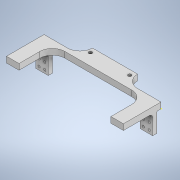
# Autodesk Inventor part: suport sfoara usa
Saved by Autodesk Inventor 2022.6 (Build 266554000, 554)
## iProperties
Created: 2025-02-05
Part Number: suport sfoara usa
Material: Generic
Document SubType Name: Modeling
Designer: Dragos Macovei
Density: 1 g/cm^3
Appearance: Default
Author: Dragos Macovei
Autodesk Inventor part; units mm, degrees
ref_plane "YZ Plane" through (0, 0, 0) normal (1, 0, 0) x (0, 1, 0)
ref_plane "XZ Plane" through (0, 0, 0) normal (0, 1, 0) x (-1, 0, 0)
ref_plane "XY Plane" through (0, 0, 0) normal (0, 0, 1) x (1, 0, 0)
sketch "Sketch1" plane through (0, 0, 0) normal (0, 0, 1) x (1, 0, 0)
  line L0 (0, 0) -> (-140, 0)
  line L1 (-140, 0) -> (-140, 7)
  line L2 (-140, 7) -> (0, 7)
  line L3 (0, 7) -> (0, 0)
  dimension "d0" = 140
  dimension "d1" = 7
  constraints: 8 end point, 2 parallel, 1 horizontal, 1 perpendicular
  measures "d0" distance of L1.end L2.end
  measures "d1" distance of L0.end L1.end
extrude "Extrusion1" add sketch "Sketch1" along normal blind 5
sketch "Sketch2" plane through (0, 0, 0) normal (0, 0, -1) x (-1, 0, 0)
  point P0 (0, 0)
sketch "Sketch3" plane through (0, 0, 5) normal (0, 0, 1) x (1, 0, 0)
  line L0 (0, 7) -> (-140, 7) projected
  line L1 (-140, 7) -> (-140, 0) projected
  line L2 (-140, 0) -> (0, 0) projected
  line L3 (0, 0) -> (0, 7) projected
  line L4 (-140, 7) -> (-140, 0) projected
  line L5 (-140, 7) -> (-125, 7)
  line L6 (-125, 7) -> (-125, -23)
  line L7 (-125, -23) -> (-140, -23)
  line L8 (-140, -23) -> (-140, 7)
  line L9 (0, 7) -> (-15, 7)
  line L10 (-15, 7) -> (-15, -23)
  line L11 (-15, -23) -> (0, -23)
  line L12 (0, -23) -> (0, 7)
  dimension "d4" = 15
  dimension "d5" = 30
  dimension "d6" = 15
  dimension "d7" = 30
  constraints: 16 end point, 4 parallel, 2 horizontal, 2 perpendicular
  measures "d4" distance of L6.end L7.end
  measures "d5" distance of L5.end L6.end
  measures "d6" distance of L11.end L10.end
  measures "d7" distance of L10.end L9.end
extrude "Extrusion2" add sketch "Sketch3" along normal blind 40 contours L3 L2 L10 L0 | L12 L11 L10 L2 | L6 L2 L1 L0 | L6 L7 L8 L2
fillet "Fillet1" radius 15 2 edges at (-125, 3.5, 5) (-15, 3.5, 5)
fillet "Fillet2" radius 1 2 edges at (-7.5, 0, 5) (-132.5, 0, 5)
sketch "Sketch4" plane through (-140, 7, 0) normal (0, 1, 0) x (1, 0, 0)
  line L0 (140, 0) -> (0, 0) projected
  line L1 (110, -5) -> (30, -5) projected
  line L2 (70, -5) -> (70, 0)
  line L3 (50, -5) -> (90, -5)
  line L4 (90, -5) -> (90, 0)
  line L5 (90, 0) -> (50, 0)
  line L6 (50, 0) -> (50, -5)
  point P0 (125, -4)
  point P1 (70, -2.5)
  point P2 (50, -2.5)
  point P3 (50, 0)
  point P4 (90, -5)
  dimension "d12" = 40
  dimension "d13" = 20
  constraints: 10 end point, 4 midpoint, 2 parallel, 2 point on line, 1 horizontal, 1 perpendicular, 1 vertical
  measures "d12" distance of L5.end L4.end
  measures "d13" distance of point (70, -2.5) point (50, -2.5)
extrude "Extrusion3" add sketch "Sketch4" along normal blind 16
sketch "Sketch7" plane through (0, 0, 45) normal (0, 0, 1) x (1, 0, 0)
  line L0 (-15, -23) -> (0, -23) projected
  line L1 (0, -23) -> (0, 7) projected
  line L2 (0, 7) -> (-15, 7) projected
  line L3 (-15, 7) -> (-15, -23) projected
  line L4 (-125, 7) -> (-140, 7) projected
  line L5 (-140, 7) -> (-140, -23) projected
  line L6 (-140, -23) -> (-125, -23) projected
  line L7 (-125, -23) -> (-125, 7) projected
  circle A0 centre (-136, -19) radius 1.35
  circle A1 centre (-136, -11) radius 1.35
  circle A2 centre (-129, -19) radius 1.35
  circle A3 centre (-129, -11) radius 1.35
  line L8 (-76.5, 23) -> (-73.5, 23) projected
  line L9 (-15, 7) -> (0, 7)
  line L10 (0, 7) -> (0, -23)
  line L11 (0, -23) -> (-15, -23)
  line L12 (-15, -23) -> (-15, 0)
  line L13 (-15, 0) -> (-15, 7)
  circle A4 centre (-4, -19) radius 1.35
  circle A5 centre (-4, -11) radius 1.35
  circle A6 centre (-11, -19) radius 1.35
  circle A7 centre (-11, -11) radius 1.35
  line L14 (-30, 7) -> (-30, 0) projected
  line L15 (-30, 7) -> (-50, 7) projected
  line L16 (-50, 7) -> (-50, 23) projected
  line L17 (-90, 23) -> (-50, 23) projected
  line L18 (-90, 7) -> (-90, 23) projected
  line L19 (-90, 7) -> (-110, 7) projected
  line L20 (-110, 0) -> (-110, 7) projected
  line L21 (-110, 0) -> (-30, 0) projected
  line L22 (-90, 23) -> (-50, 23) projected
  point P0 (0, 0)
  point P1 (-70, 23)
  point P2 (-70, 23)
  dimension "d22" = 2.7
  dimension "d23" = 2.7
  dimension "d24" = 2.7
  dimension "d25" = 2.7
  dimension "d26" = 4
  dimension "d27" = 4
  dimension "d28" = 4
  dimension "d29" = 4
  dimension "d30" = 4
  dimension "d31" = 4
  dimension "d32" = 18
  dimension "d33" = 18
  dimension "d36" = 20
  dimension "d37" = 4
  dimension "d38" = 4
  dimension "d39" = 4
  dimension "d42" = 4
  dimension "d43" = 18
  dimension "d44" = 18
  constraints: 10 end point, 8 centre point, 2 midpoint
  measures "d22" diameter of A0
  measures "d23" diameter of A1
  measures "d24" diameter of A2
  measures "d25" diameter of A3
  measures "d26" distance from line of L5 A0.centre
  measures "d27" distance from line of L5 A1.centre
  measures "d28" distance from line of L7 A3.centre
  measures "d29" distance from line of L7 A2.centre
  measures "d30" distance from line of L6 A0.centre
  measures "d31" distance from line of L6 A2.centre
  measures "d32" distance from line of L4 A3.centre
  measures "d33" distance from line of L4 A1.centre
  measures "d36" distance of L16.end point (-70, 23)
  measures "d37" distance from line of L1 A5.centre
  measures "d38" distance from line of L0 A4.centre
  measures "d39" distance from line of L1 A4.centre
  measures "d42" distance from line of L0 A6.centre
  measures "d43" distance from line of L2 A7.centre
  measures "d44" distance from line of L2 A5.centre
extrude "Extrusion6" cut sketch "Sketch7" against normal through all contours A0 | A1 | A2 | A3 | A4 | A5 | A6 | A7
sketch "Sketch8" plane through (0, 0, 0) normal (0, 0, -1) x (-1, 0, 0)
  line L0 (0, 7) -> (50, 7) projected
  line L1 (0, 0) -> (0, 7) projected
  line L2 (140, 0) -> (0, 0) projected
  line L3 (140, 7) -> (140, 0) projected
  line L4 (90, 7) -> (140, 7) projected
  line L5 (90, 7) -> (90, 23) projected
  line L6 (50, 23) -> (90, 23) projected
  line L7 (50, 7) -> (50, 23) projected
  line L8 (110, 0) -> (30, 0) projected
  line L9 (50, 7) -> (43, 7)
  line L10 (43, 7) -> (43, 0)
  line L11 (43, 0) -> (50, 0)
  line L12 (50, 0) -> (50, 7)
  line L13 (90, 7) -> (97, 7)
  line L14 (97, 7) -> (97, 0)
  line L15 (97, 0) -> (90, 0)
  line L16 (90, 0) -> (90, 7)
  point P0 (97, 3.5)
  point P1 (90, 3.5)
  point P2 (43, 3.5)
  point P3 (50, 3.5)
  dimension "d45" = 7
  dimension "d46" = 7
  constraints: 16 end point, 4 midpoint, 4 parallel, 2 horizontal, 2 perpendicular, 2 point on line
  measures "d45" distance of point (97, 3.5) point (90, 3.5)
  measures "d46" distance of point (43, 3.5) point (50, 3.5)
extrude "Extrusion7" add sketch "Sketch8" along normal blind 15 contours L0 L12 L2 L10 | L16 L4 L14 L2
fillet "Fillet4" radius 15 2 edges at (-43, 3.5, 0) (-97, 3.5, 0)
sketch "Sketch9" plane through (0, 7, 45) normal (0, 1, 0) x (1, 0, 0)
  line L0 (-90, 40) -> (-90, 45) projected
  line L1 (-90, 45) -> (-90, 60) projected
  line L2 (-97, 60) -> (-90, 60) projected
  arc A0 (-112, 45) -> (-97, 60) centre (-112, 60) ccw projected
  line L3 (-112, 45) -> (-140, 45) projected
  line L4 (-140, 45) -> (-140, 0) projected
  line L5 (-125, 0) -> (-140, 0) projected
  arc A1 (-110, 40) -> (-125, 25) centre (-110, 25) ccw projected
  line L6 (-90, 40) -> (-110, 40) projected
  line L7 (-50, 45) -> (-50, 40) projected
  line L8 (-30, 40) -> (-50, 40) projected
  arc A2 (-15, 25) -> (-30, 40) centre (-30, 25) ccw projected
  line L9 (0, 0) -> (-15, 0) projected
  line L10 (0, 45) -> (0, 0) projected
  line L11 (0, 45) -> (-28, 45) projected
  arc A3 (-43, 60) -> (-28, 45) centre (-28, 60) ccw projected
  line L12 (-50, 60) -> (-43, 60) projected
  line L13 (-50, 45) -> (-50, 60) projected
  circle A4 centre (-46.5, 54) radius 2
  circle A5 centre (-93.5, 54) radius 2
  line L14 (-15, 25) -> (-15, 0) projected
  line L15 (-125, 25) -> (-125, 0) projected
  point P0 (-46.5, 60)
  point P1 (-93.5, 60)
  dimension "d50" = 4
  dimension "d51" = 4
  dimension "d54" = 6
  dimension "d55" = 6
  constraints: 2 centre point, 2 midpoint
  measures "d50" diameter of A5
  measures "d51" diameter of A4
  measures "d54" distance of point (-46.5, 60) A4.centre
  measures "d55" distance of point (-93.5, 60) A5.centre
extrude "Extrusion8" cut sketch "Sketch9" against normal through all contours A4 | A5
sketch "Sketch10" plane through (0, 0, 45) normal (0, 0, 1) x (1, 0, 0)
  line L0 (-28, 0) -> (0, 0) projected
  line L1 (-140, 0) -> (-112, 0) projected
  line L2 (-15, 7) -> (-15, -23) projected
  line L3 (0, -23) -> (0, 7) projected
  line L4 (-125, -23) -> (-125, 7) projected
  line L5 (-140, 7) -> (-140, -23) projected
  circle A0 centre (-136, -19) radius 1.35 projected
  circle A1 centre (-136, -11) radius 1.35 projected
  circle A2 centre (-129, -19) radius 1.35 projected
  circle A3 centre (-129, -11) radius 1.35 projected
  line L6 (-125, 7) -> (-140, 7) projected
  line L7 (-140, 7) -> (-140, -23) projected
  line L8 (-140, -23) -> (-125, -23) projected
  line L9 (-125, -23) -> (-125, 7) projected
  circle A4 centre (-11, -19) radius 1.35 projected
  circle A5 centre (-11, -11) radius 1.35 projected
  circle A6 centre (-4, -19) radius 1.35 projected
  circle A7 centre (-4, -11) radius 1.35 projected
  line L10 (-15, -23) -> (0, -23) projected
  line L11 (0, -23) -> (0, 7) projected
  line L12 (0, 7) -> (-15, 7) projected
  line L13 (-15, 7) -> (-15, -23) projected
  line L14 (-125, -23) -> (-140, -23)
  line L15 (-140, -23) -> (-140, 0)
  line L16 (-140, 0) -> (-125, 0)
  line L17 (-125, 0) -> (-125, -23)
  line L18 (-15, -23) -> (0, -23)
  line L19 (0, -23) -> (0, 0)
  line L20 (0, 0) -> (-15, 0)
  line L21 (-15, 0) -> (-15, -23)
  constraints: 16 end point, 4 parallel, 2 horizontal, 2 perpendicular
extrude "Extrusion9" cut sketch "Sketch10" against normal blind 35 contours L0 L3 L10 L2 | L1 L4 L8 L5
fillet "Fillet5" radius 4 2 edges at (-132.5, 0, 10) (-7.5, 0, 10)
sketch "Sketch11" plane through (0, 0, 0) normal (0, 0, -1) x (-1, 0, 0)
  line L0 (90, 0) -> (90, 7) projected
  line L1 (90, 7) -> (90, 23) projected
  line L2 (50, 23) -> (90, 23) projected
  line L3 (50, 7) -> (50, 23) projected
  line L4 (50, 7) -> (50, 0) projected
  line L5 (90, 0) -> (50, 0) projected
  line L6 (90, 0) -> (50, 0)
  line L7 (50, 0) -> (50, 7)
  line L8 (50, 7) -> (90, 7)
  line L9 (90, 7) -> (90, 0)
  point P0 (0, 0)
  constraints: 8 end point, 2 parallel, 1 horizontal, 1 perpendicular
extrude "Extrusion10" add sketch "Sketch11" along normal up to surface (15 mm away) contours L5 L4 L8 L0
sketch "Sketch12" plane through (0, 0, 0) normal (0, 0, -1) x (-1, 0, 0)
  line L0 (50, 7) -> (90, 7) projected
  line L1 (90, 7) -> (90, 23) projected
  line L2 (50, 23) -> (90, 23) projected
  line L3 (50, 7) -> (50, 23) projected
  point P0 (0, 0)
extrude "Extrusion11" cut sketch "Sketch12" against normal through all
body "Solid1"
